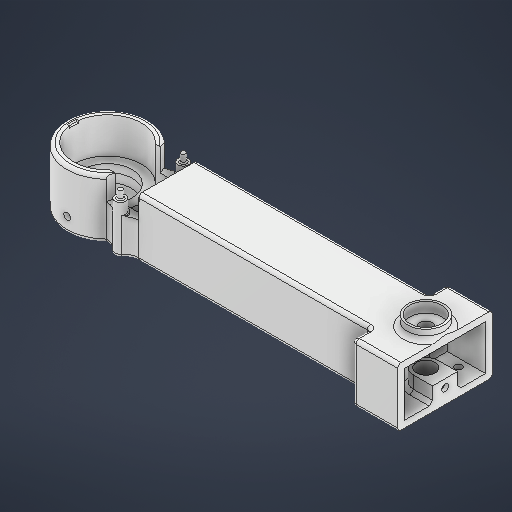
# Autodesk Inventor part: Плечо_переднее_3BAR
Saved by Autodesk Inventor 2026 (Build 300175050, 175E)
## iProperties
Created: 2026-10-15
Part Number: Плечо_переднее_3BAR
Material: Пластик АБС
Document SubType Name: Modeling
Designer: Ваня
Density: 1.06 g/cm^3
Appearance: Гладкий — белый
Author: Ваня
Autodesk Inventor part; units mm, degrees
ref_plane "XZ Plane" through (0, 0, 0) normal (0, 1, 0) x (-1, 0, 0)
ref_plane "XY Plane" through (0, 0, 0) normal (0, 0, 1) x (1, 0, 0)
sketch "Эскиз1" plane through (0, 0, 0) normal (1, 0, 0) x (0, 1, 0)
  line L0 (-10, -10) -> (10, -10)
  line L1 (10, -10) -> (10, 10)
  line L2 (10, 10) -> (-10, 10)
  line L3 (-10, 10) -> (-10, -10)
  line L4 (-10, -10) -> (10, 10) construction
  line L5 (10, -10) -> (-10, 10) construction
  line L6 (-13, 13) -> (13, 13)
  line L7 (13, 13) -> (13, -13)
  line L8 (13, -13) -> (-13, -13)
  line L9 (-13, -13) -> (-13, 13)
  line L10 (-13, 13) -> (13, -13) construction
  line L11 (13, 13) -> (-13, -13) construction
  point P0 (0, 0)
  dimension "d0" = 20
  dimension "d1" = 20
  dimension "d2" = 26
  dimension "d3" = 26
  constraints: 24 end point, 4 midpoint, 4 parallel, 2 horizontal, 2 perpendicular
  measures "d0" distance of L2.end L1.end
  measures "d1" distance of L1.end L0.end
  measures "d2" distance of L7.end L8.end
  measures "d3" distance of L6.end L7.end
extrude "Выдавливание1" add sketch "Эскиз1" along normal blind 125
sketch "Эскиз2" plane through (0, -13, -13) normal (0, -1, 0) x (1, 0, 0)
  line L0 (125, 3) -> (125, 23) projected
  line L1 (125, 13) -> (125, -8)
  line L2 (125, -8) -> (145, -8)
  line L3 (145, -8) -> (145, 34)
  line L4 (145, 34) -> (125, 34)
  line L5 (125, 34) -> (125, 13)
  point P0 (0, 13)
  dimension "d6" = 21
  dimension "d7" = 20
  dimension "d8" = 42
  constraints: 10 end point, 2 collinear, 2 perpendicular, 1 horizontal, 1 midpoint
  measures "d6" distance of L1.start L1.end
  measures "d7" distance of L1.end L2.end
  measures "d8" distance of L2.end L3.end
extrude "Выдавливание2" add sketch "Эскиз2" against normal blind 26
sketch "Эскиз3" plane through (145, -13, 21) normal (1, 0, 0) x (0, 0, -1)
  line L0 (3, 23) -> (39, 23)
  line L1 (39, 23) -> (39, 3)
  line L2 (39, 3) -> (3, 3)
  line L3 (3, 3) -> (3, 23)
  line L4 (3, 23) -> (39, 3) construction
  line L5 (39, 23) -> (3, 3) construction
  point P0 (21, 13)
  dimension "d11" = 36
  dimension "d12" = 20
  constraints: 12 end point, 2 midpoint, 2 parallel, 1 horizontal, 1 perpendicular
  measures "d11" distance of L1.end L2.end
  measures "d12" distance of L0.end L1.end
extrude "Выдавливание3" cut sketch "Эскиз3" against normal blind 17
sketch "Эскиз4" plane through (0, 0, 0) normal (-1, 0, 0) x (0, 0, 1)
  line L0 (-10, 10) -> (10, 10)
  line L1 (10, 10) -> (10, -10)
  line L2 (10, -10) -> (-10, -10)
  line L3 (-10, -10) -> (-10, 10)
  line L4 (-10, 10) -> (10, -10) construction
  line L5 (10, 10) -> (-10, -10) construction
  point P0 (0, 0)
  constraints: 12 end point, 2 midpoint, 2 parallel, 1 horizontal, 1 perpendicular
extrude "Выдавливание4" cut sketch "Эскиз4" against normal blind 145
sketch "Эскиз5" plane through (0, -13, -13) normal (0, -1, 0) x (1, 0, 0)
  line L0 (145, 34) -> (125, 34) projected
  line L1 (125, 34) -> (125, 31)
  line L2 (125, 26) -> (125, 34) projected
  line L3 (128, 23) -> (128, 31) projected
  line L4 (125, 31) -> (128, 31)
  line L5 (128, 31) -> (136.5, 31)
  line L6 (136.5, 31) -> (136.5, 13)
  circle A0 centre (136.5, 13) radius 4.05
  line L7 (136.5, 13) -> (136.5, 27.5)
  line L8 (136.5, 13) -> (136.5, -1.5)
  circle A1 centre (136.5, -1.5) radius 1.55
  circle A2 centre (136.5, 27.5) radius 1.55
  point P0 (0, 13)
  dimension "d17" = 3
  dimension "d18" = 3
  dimension "d19" = 8.5
  dimension "d20" = 18
  dimension "d21" = 8.1
  dimension "d22" = 14.5
  dimension "d23" = 14.5
  dimension "d24" = 3.1
  dimension "d25" = 3.1
  constraints: 12 end point, 3 centre point, 3 coincident, 3 point on line, 1 perpendicular, 1 vertical
  measures "d17" distance of L0.end L1.end
  measures "d18" distance of L1.end L3.end
  measures "d19" distance of L3.end L5.end
  measures "d20" distance of L5.end L6.end
  measures "d21" diameter of A0
  measures "d22" distance of L7.start L7.end
  measures "d23" distance of L7.start L8.end
  measures "d24" diameter of A1
  measures "d25" diameter of A2
extrude "Выдавливание5" cut sketch "Эскиз5" against normal blind 5
sketch "Эскиз6" plane through (0, -10, 10) normal (0, 1, 0) x (1, 0, 0)
  circle A0 centre (136.5, 10) radius 4.05 projected
  circle A1 centre (136.5, 10) radius 4.05
  circle A2 centre (136.5, 10) radius 5.55
  line L0 (145, 31) -> (145, -11) projected
  line L1 (140.55, 10) -> (145, 10)
  line L2 (136.5, 4.45) -> (145, 4.45)
  line L3 (136.5, 15.55) -> (145, 15.55)
  line L4 (145, 4.45) -> (145, 15.55)
  point P0 (0, 10)
  dimension "d28" = 11.1
  constraints: 8 end point, 2 coincident, 2 perpendicular, 2 point on circle, 2 point on line, 2 tangent, 1 centre point, 1 collinear, 1 horizontal alignment, 1 midpoint, 2 other
  measures "d28" diameter of A2
extrude "Выдавливание6" add sketch "Эскиз6" along normal blind 7
chamfer "Фаска1" distance 1.5 angle 45 3 edges at (140.75, -10, 5.55) (130.95, -10, 0) (140.75, -10, -5.55)
ref_plane "РабПлоскость1" through (140.55, -13, 21) normal (1, 0, 0) x (0, 0, -1)
sketch "Эскиз7" plane through (140.55, -13, 21) normal (1, 0, 0) x (0, 0, -1)
  line L0 (15.45, 10) -> (26.55, 10) projected
  line L1 (21, 10) -> (21, 6.5)
  line L2 (21, 6.5) -> (21, 9.3)
  line L3 (21, 9.3) -> (24.1398, 9.3)
  line L4 (24.1398, 9.3) -> (17.4837, 9.3)
  line L5 (20.145, 10.6191) -> (16.817, 4.8548)
  line L6 (17.0052, 7.8191) -> (20.3333, 2.0548)
  line L7 (17.8602, 3.7) -> (24.5163, 3.7)
  line L8 (21.855, 2.3809) -> (25.183, 8.1452)
  line L9 (24.9948, 5.1809) -> (21.6667, 10.9452)
  circle A0 centre (21, 6.5) radius 1.75
  point P0 (21, 13)
  point P1 (19.3834, 9.3)
  point P2 (17.7668, 6.5)
  point P3 (19.3834, 3.7)
  point P4 (22.6166, 3.7)
  point P5 (24.2332, 6.5)
  point P6 (22.6166, 9.3)
  dimension "d36" = 3.5
  dimension "d37" = 2.8
  dimension "d40" = 360
  dimension "d42" = 3.5
  constraints: 18 end point, 2 point on line, 1 centre point, 1 coincident, 1 horizontal, 1 midpoint, 1 vertical, 19 other
  measures "d36" distance of L1.start L1.end
  measures "d37" distance of L1.end L2.end
  measures "d42" diameter of A0
extrude "Выдавливание7" cut sketch "Эскиз7" along normal blind 7 contours A0
extrude "Выдавливание8" cut sketch "Эскиз7" against normal blind 1 contours A0
extrude "Выдавливание9" cut sketch "Эскиз7" along normal mid plane 5.5 contours L4 L3 L9 L8 L7 L6 L5
sketch "Эскиз8" plane through (0, 13, 13) normal (0, 1, 0) x (1, 0, 0)
  line L0 (128, -5) -> (128, 3) projected
  line L1 (128, -5) -> (136.5, -5)
  line L2 (145, -5) -> (128, -5) projected
  circle A0 centre (136.5, 13) radius 4.05 projected
  line L3 (136.5, -5) -> (136.5, 13)
  circle A1 centre (136.5, 13) radius 7.1
  circle A2 centre (136.5, 13) radius 2.75
  point P0 (0, 13)
  dimension "d49" = 14.2
  dimension "d50" = 5.5
  constraints: 4 end point, 2 centre point, 2 coincident, 1 midpoint, 1 vertical
  measures "d49" diameter of A1
  measures "d50" diameter of A2
extrude "Выдавливание10" cut sketch "Эскиз8" against normal blind 2 contours A0 | A1 | A2
extrude "Выдавливание11" cut sketch "Эскиз8" against normal blind 5 contours A2
sketch "Эскиз10" plane through (0, 13, 13) normal (0, 1, 0) x (1, 0, 0)
  line L0 (0, 13) -> (-5, 13)
  circle A0 centre (-5, 13) radius 15
  circle A1 centre (-5, 13) radius 18
  dimension "d57" = 5
  dimension "d58" = 30
  dimension "d59" = 36
  constraints: 2 centre point, 2 coincident, 2 end point, 1 horizontal
  measures "d57" distance of L0.start L0.end
  measures "d58" diameter of A0
  measures "d59" diameter of A1
extrude "Выдавливание12" add sketch "Эскиз10" against normal blind 26
extrude "Выдавливание13" cut sketch "Эскиз10" against normal blind 26 contours A0
sketch "Эскиз11" plane through (128, -13, 21) normal (1, 0, 0) x (0, 0, -1)
  line L0 (31, 23) -> (31, 3) projected
  line L1 (11, 23) -> (31, 23)
  line L2 (31, 23) -> (31, 3)
  line L3 (31, 3) -> (11, 3)
  line L4 (11, 3) -> (11, 23)
  line L5 (11, 23) -> (31, 3) construction
  line L6 (31, 23) -> (11, 3) construction
  point P0 (21, 13)
  constraints: 12 end point, 2 midpoint, 2 parallel, 1 horizontal, 1 perpendicular
extrude "Выдавливание14" cut sketch "Эскиз11" against normal blind 130.5
sketch "Эскиз12" plane through (125, -13, -21) normal (0, -1, 0) x (1, 0, 0)
  circle A0 centre (-130, 21) radius 15
  point P0 (-125, 21)
  constraints: 1 centre point
extrude "Выдавливание15" add sketch "Эскиз12" against normal blind 3
ref_plane "РабПлоскость2" through (-5, 0, 0) normal (1, 0, 0) x (0, 1, 0)
sketch "Эскиз14" plane through (-5, 0, 0) normal (1, 0, 0) x (0, 1, 0)
  line L0 (-10, -7.05) -> (-10, 7.05) projected
  line L1 (-10, 0) -> (-10, 10.6)
  line L2 (-10, 0) -> (-6.45, 0)
  line L3 (-6.45, 0) -> (-6.45, 11.1)
  line L4 (-6.45, 0) -> (-2.9, 0)
  line L5 (-6.45, 0) -> (-2.9, 0) construction
  line L6 (-2.9, 0) -> (-2.9, 10.6)
  line L7 (-2.9, 10.6) -> (-2.9, 10.9)
  arc A0 (-2.9, 10.9) -> (-6.45, 11.1) centre (-7.694, -42.5881) ccw
  arc A1 (-6.45, 11.1) -> (-10, 10.6) centre (-6.45, -1.7525) ccw
  line L8 (-2.9, 10.6) -> (-2.9, 13.1)
  arc A2 (-2.9, 13.1) -> (-10, 13.1) centre (-6.45, 0.7475) ccw
  arc A3 (-6.45, 11.1) -> (-10, 10.6) centre (-6.45, -1.7525) ccw
  line L9 (-10, 0) -> (20, 0)
  line L10 (-10, 10.6) -> (-10, 13.1)
  line L11 (-10, 7.05) -> (-10, 18) projected
  point P0 (0, 0)
  dimension "d80" = 10.6
  dimension "d81" = 3.55
  dimension "d82" = 11.1
  dimension "d83" = 3.55
  dimension "d84" = 0
  dimension "d85" = 10.6
  dimension "d86" = 0.3
  dimension "d87" = 2.5
  dimension "d88" = 30
  constraints: 20 end point, 8 point on circle, 4 centre point, 4 horizontal, 3 collinear, 2 parallel, 2 vertical, 1 midpoint
  measures "d80" distance of L1.start L1.end
  measures "d81" distance of L1.start L2.end
  measures "d82" distance of L2.end L3.end
  measures "d83" distance of L2.end L4.end
  measures "d84" distance between parallel lines of L4 L5
  measures "d85" distance of L4.end L6.end
  measures "d86" distance of L6.end L7.end
  measures "d87" distance of L6.end L8.end
  measures "d88" distance of L1.start L9.end
revolve "Вращение2" add sketch "Эскиз14" angle 360 about axis through (-5, -10, 0) along (0, 1, 0) contours L10 A2 L8 A0 A1
ref_plane "РабПлоскость3" through (-5, 0, 0) normal (1, 0, 0) x (0, 1, 0)
sketch "Эскиз17" plane through (-5, 0, 0) normal (1, 0, 0) x (0, 1, 0)
  arc A0 (-2.9, 13.1) -> (-10, 13.1) centre (-6.45, 0.7475) ccw projected
  line L0 (-10, 13.1) -> (-10, 15)
  line L1 (-10, 15) -> (13, 15) projected
  line L2 (-2.9, -13.1) -> (-2.9, 13.1) projected
  line L3 (-2.9, 13.1) -> (-2.9, 15)
  line L4 (-2.9, 15) -> (-10, 15)
  arc A1 (-2.9, 13.1) -> (-10, 13.1) centre (-6.45, 0.7475) ccw
  line L5 (-2.9, 15) -> (-10, 15)
  line L6 (-44.8368, 0) -> (113.3052, 0)
  point P0 (0, 0)
  constraints: 10 end point, 3 point on circle, 2 vertical, 1 centre point, 1 collinear, 1 concentric, 1 horizontal, 1 perpendicular, 1 point on line
revolve "Вращение4" add sketch "Эскиз17" angle 360 mid plane about axis through (-5, -44.8368, 0) along (0, 1, 0)
sketch "Эскиз18" plane through (0, 0, 0) normal (0, 0, 1) x (1, 0, 0)
  line L0 (6.1, -6.45) -> (-16.1, -6.45) projected
  line L1 (-5, -6.45) -> (-5, -3.65)
  line L2 (5.6, -10) -> (-15.6, -10) projected
  line L3 (-5, -3.65) -> (-3, -3.65)
  line L4 (-3, -3.65) -> (-7, -3.65)
  line L5 (-7.4249, -5.05) -> (-6.4249, -3.3179)
  line L6 (-6.4249, -3.3179) -> (-8.4249, -6.7821)
  line L7 (-7.4249, -7.85) -> (-8.4249, -6.1179)
  line L8 (-8.4249, -6.1179) -> (-6.4249, -9.5821)
  line L9 (-5, -9.25) -> (-7, -9.25)
  line L10 (-7, -9.25) -> (-3, -9.25)
  line L11 (-2.5751, -7.85) -> (-3.5751, -9.5821)
  line L12 (-3.5751, -9.5821) -> (-1.5751, -6.1179)
  line L13 (-2.5751, -5.05) -> (-1.5751, -6.7821)
  line L14 (-1.5751, -6.7821) -> (-3.5751, -3.3179)
  circle A0 centre (-5, -6.45) radius 1.45
  point P0 (0, 0)
  point P1 (-1.7668, -6.45)
  point P2 (-3.3834, -3.65)
  point P3 (-6.6166, -3.65)
  point P4 (-8.2332, -6.45)
  point P5 (-6.6166, -9.25)
  point P6 (-3.3834, -9.25)
  dimension "d108" = 2.8
  dimension "d109" = 2
  dimension "d110" = 4
  dimension "d113" = 360
  dimension "d115" = 2.9
  constraints: 26 end point, 6 point on line, 1 centre point, 1 coincident, 1 horizontal, 1 midpoint, 1 perpendicular, 31 other
  measures "d108" distance of L1.start L1.end
  measures "d109" distance of L1.end L3.end
  measures "d110" distance of L3.end L4.end
  measures "d115" diameter of A0
extrude "Выдавливание18" cut sketch "Эскиз18" along normal blind 13.6
extrude "Выдавливание19" cut sketch "Эскиз18" along normal blind 20 contours A0 L0 | L0 L1 A0 | L0 A0 L1
sketch "Эскиз19" plane through (125, 13, 21) normal (0, 1, 0) x (1, 0, 0)
  arc A0 (-118.8197, 31) -> (-118.8197, 11) centre (-130, 21) ccw projected
  circle A1 centre (-130, 21) radius 12.3
  line L0 (-117.5501, 8) -> (0, 8) projected
  line L1 (-117.5501, 8) -> (-117.5501, 11)
  line L2 (-118.8197, 11) -> (3, 11) projected
  line L3 (-117.5501, 11) -> (-110.3001, 11)
  line L4 (-110.3001, 11) -> (-110.3001, 14)
  line L5 (-110.3001, 14) -> (-110.3001, 7)
  circle A2 centre (-110.3001, 7) radius 2.5
  arc A3 (-118.8197, 11) -> (-118.8197, 31) centre (-130, 21) ccw projected
  line L6 (-115, 21) -> (-110, 21)
  circle A4 centre (-110.3001, 35) radius 2.5
  circle A5 centre (-110.3001, 7) radius 7.3186
  line L7 (-117.5501, 34) -> (0, 34) projected
  circle A6 centre (-110.3001, 35) radius 7.3186
  point P0 (-125, 21)
  dimension "d120" = 24.6
  dimension "d121" = 7.25
  dimension "d122" = 3
  dimension "d123" = 7
  dimension "d124" = 5
  dimension "d126" = 5
  constraints: 10 end point, 4 coincident, 3 centre point, 2 point on line, 2 vertical, 1 horizontal, 1 perpendicular, 1 point on circle, 1 symmetric about line, 7 other
  measures "d120" diameter of A1
  measures "d121" distance of L1.end L3.end
  measures "d122" distance of L3.end L4.end
  measures "d123" distance of L4.end L5.end
  measures "d124" diameter of A2
  measures "d126" distance of L6.start L6.end
extrude "Выдавливание24" cut sketch "Эскиз19" against normal blind 9.6 contours A5 L2 L5 A2 L0 | L0 A2 A5 | A2 L5 L0 | L0 A2 | A5 L2 | L5 A2 L0 | L5 L2 A5 L0 A2 | A4 L7 | A4 L7 A6 | L7 A4 | A4 L7 A6
sketch "Эскиз22" plane through (125, 3.4, 21) normal (0, 1, 0) x (1, 0, 0)
  line L0 (-115, 21) -> (-110, 21) projected
  circle A0 centre (-110.3001, 7) radius 2.4
  circle A1 centre (-110.3001, 7) radius 1
  circle A2 centre (-110.3001, 35) radius 2.4
  circle A3 centre (-110.3001, 35) radius 1
  point P0 (-125, 21)
  dimension "d140" = 4.8
  dimension "d141" = 2
  constraints: 4 centre point, 3 coincident, 2 symmetric about line, 2 other
  measures "d140" diameter of A0
  measures "d141" diameter of A1
extrude "Выдавливание25" add sketch "Эскиз22" along normal blind 5
extrude "Выдавливание26" add sketch "Эскиз22" against normal blind 16.4 contours A0 | A1 | A2 | A3
fillet "Сопряжение9" radius 7 4 edges at (12.5182, -4.8, 13) (16.8816, -4.8, 13) (16.8816, -4.8, -13) (12.5182, -4.8, -13)
sketch "Эскиз23" plane through (125, 13, 21) normal (0, 1, 0) x (1, 0, 0)
  line L0 (-118.8197, 31) -> (3, 31) projected
  arc A0 (-117.5501, 34) -> (-116.4289, 31) centre (-110.3001, 35) ccw projected
  line L1 (-118.8197, 31) -> (-116.4289, 31)
  arc A1 (-104.1713, 31) -> (-103.0501, 34) centre (-110.3001, 35) ccw projected
  line L2 (-103.0501, 34) -> (-117.5501, 34)
  line L3 (-103.0641, 8) -> (0, 8) projected
  line L4 (-103.0501, 34) -> (-103.0641, 8)
  line L5 (-103.0641, 8) -> (-117.5501, 8.0078)
  line L6 (-116.4289, 11) -> (-104.1713, 11) projected
  arc A2 (-116.4289, 11) -> (-117.5501, 8) centre (-110.3001, 7) ccw projected
  arc A3 (-116.4289, 11) -> (-117.5501, 8) centre (-110.3001, 7) ccw
  line L7 (-118.8197, 11) -> (3, 11) projected
  line L8 (-116.4289, 11) -> (-118.8197, 11)
  arc A4 (-118.8197, 11) -> (-118.8197, 31) centre (-130, 21) ccw
  line L9 (-116.4289, 11) -> (-116.4305, 8.0072)
  arc A5 (-112.1476, 5.4681) -> (-117.5361, 8) centre (-117.5361, 1) ccw projected
  line L10 (-116.4305, 8.0072) -> (-117.5361, 8)
  line L11 (-118.8197, 31) -> (-118.8197, 11)
  point P0 (-125, 21)
  point P1 (-117.549, 8.0078)
  constraints: 16 end point, 4 point on circle, 2 centre point, 2 horizontal, 2 perpendicular, 1 collinear, 1 point on line, 1 vertical
extrude "Выдавливание27" cut sketch "Эскиз23" against normal blind 3 contours L0 L4 L7 L6 A4 | A0 L2 A1 L0 | A1 L4 L0 | L9 L5 A2 | L6 L7 L4 L5 L9
move faces "Перенос1" translate (0, -0.5, 0) faces at (14.6148, 3.4, -10.5379) (14.6148, 3.4, 10.5379)
sketch "Эскиз24" plane through (8.5711, 2.9, -10) normal (0, 1, 0) x (1, 0, 0)
  circle A0 centre (6.1288, 4) radius 2.4 projected
  arc A1 (3.1633, 4.4536) -> (9.0943, 4.4536) centre (6.1288, 4) ccw
  arc A2 (-1.1072, 3) -> (4.2813, 5.5319) centre (-1.1072, 10) ccw projected
  arc A3 (7.9763, 5.5319) -> (13.3648, 3) centre (13.3648, 10) ccw projected
  line L0 (13.3665, -20) -> (13.3772, 0) projected
  line L1 (13.3718, -10) -> (11.26, -10)
  circle A4 centre (6.1288, -24) radius 2.4
  arc A5 (9.0943, -24.4536) -> (3.1633, -24.4536) centre (6.1288, -24) ccw
  arc A6 (4.2813, -25.5319) -> (-1.1072, -23) centre (-1.1072, -30) ccw
  arc A7 (13.3648, -23) -> (7.9763, -25.5319) centre (13.3648, -30) ccw
  point P0 (-8.5711, -10)
  dimension "d152" = 6
  constraints: 12 point on circle, 10 symmetric about line, 5 centre point, 2 coincident, 2 end point, 1 horizontal, 1 midpoint, 4 other
  measures "d152" diameter of A1
extrude "Выдавливание28" add sketch "Эскиз24" along normal blind 0.5 contours A0 A3 A1 A2 | A4 A6 A5 A7
fillet "Сопряжение10" radius 1.5 25 edges at (73.4749, 13, -13) (73.4749, 13, 13) (18.9591, -13, 13.6645) (14.6999, -13, 16.4) (10.4407, -13, 13.6645) (7.4569, -13, 13) (73.468, -13, 13) (18.9591, -13, -13.6645) (14.6999, -13, -16.4) (10.4407, -13, -13.6645) (7.4569, -13, -13) (73.468, -13, -13) (135, -13, -21) (125, 0, -21) (125, 0, -13) (135, 13, -21) (125, 13, -17) (125, -13, -17) (125, 13, 17) (125, -13, 17) (125, 0, 21) (135, -13, 21) (135, 13, 21) (-23, -13, 0) (125, 0, 13)
fillet "Сопряжение11" radius 1.5 1 edges at (-23, 13, 0)
sketch "Эскиз25" plane through (-5, 13, 0) normal (0, 1, 0) x (1, 0, 0)
  arc A0 (11.1803, 10) -> (11.1803, -10) centre (0, 0) ccw projected
  line L0 (-15, 0) -> (-15, 2)
  line L1 (-15, 0) -> (-13, 0) construction
  line L2 (-15, 2) -> (-14.8661, 2)
  line L3 (-15, 0) -> (-15.5, 0)
  line L4 (-15, 0) -> (-15, -2)
  line L5 (-15, -2) -> (-14.8661, -2)
  line L6 (-14.8661, 2) -> (-15.8661, 2)
  line L7 (-15.8661, 2) -> (-15.8661, -2)
  line L8 (-15.8661, -2) -> (-15, -2)
  point P0 (5, 0)
  dimension "d157" = 2
  dimension "d158" = 90
  dimension "d159" = 0.5
  dimension "d160" = 1
  constraints: 18 end point, 3 horizontal, 3 perpendicular, 2 point on circle, 2 symmetric about line, 1 collinear, 1 tangent, 1 vertical
  measures "d157" distance of L0.start L0.end
  measures "d158" angle of L1 L0
  measures "d159" distance of L0.start L3.end
  measures "d160" distance of L2.end L6.end
extrude "Выдавливание29" cut sketch "Эскиз25" against normal blind 1
sketch "Эскиз27" plane through (14.6999, 3.4, 14) normal (0, 1, 0) x (1, 0, 0)
  circle A0 centre (0, 0) radius 1 projected
  circle A1 centre (0, 28) radius 1 projected
  point P0 (-14.6999, 14)
extrude "Выдавливание30" add sketch "Эскиз27" along normal blind 8.5
fillet "Сопряжение12" radius 0.5 2 edges at (13.6999, 8.4, 14) (13.6999, 8.4, -14)
sketch "Эскиз29" plane through (21.9367, 13, 11.5) normal (0, 1, 0) x (1, 0, 0)
  circle A0 centre (114.5633, 11.5) radius 2.75 projected
  circle A1 centre (114.5633, 11.5) radius 7.1
  circle A2 centre (114.5633, 11.5) radius 2.75 projected
  point P0 (-21.9367, 11.5)
  constraints: 1 centre point, 1 coincident
extrude "Выдавливание31" add sketch "Эскиз29" against normal blind 2
sketch "Эскиз30" plane through (21.9367, 13, 11.5) normal (0, 1, 0) x (1, 0, 0)
  circle A0 centre (114.5633, 11.5) radius 2.75 projected
  circle A1 centre (114.5633, 11.5) radius 7.1
  circle A2 centre (114.5633, 11.5) radius 8.1
  point P0 (-21.9367, 11.5)
  dimension "d168" = 14.2
  dimension "d169" = 16.2
  constraints: 2 centre point, 2 coincident
  measures "d168" diameter of A1
  measures "d169" diameter of A2
extrude "Выдавливание32" add sketch "Эскиз30" along normal blind 4.5 contours A2
fillet "Сопряжение13" radius 2 1 edges at (128.4, 13, 0)
offset faces "Размер2" outward -0.05 faces at (138.2874, -7.5, 3.6342)
offset faces "Размер3" outward 0.25 faces at (144.4333, -6.2193, -1.7273)
